toytalker_mini_v0.6.4_sw02 (Autodesk Fusion 360 design; units mm, degrees)
part number: 2026-11-13-12-19-30-729
Autodesk Fusion 360 part; units mm, degrees
ref_plane "作業平面1" through (0, 0, 0) normal (0, 0, 1) x (1, 0, 0)
sketch "スケッチ1" plane through (0, 0, 0) normal (0, 0, 1) x (1, 0, 0)
  line L0 (-1.5, -1.5) -> (41.5, -1.5)
  line L1 (41.5, -1.5) -> (41.5, 41.5)
  line L2 (41.5, 41.5) -> (-1.5, 41.5)
  line L3 (-1.5, 41.5) -> (-1.5, -1.5)
  dimension "board" = 40
  dimension "gap" = 0.2
  dimension "wall" = 1.3
  dimension "inner_h" = 9.4
  dimension "board_top" = 5
  dimension "lid_t" = 1.3
  dimension "corner_r" = 1.3
  dimension "hook_len" = 2.6
  dimension "hook_w" = 6
  dimension "hook_t" = 1
  dimension "barb" = 0.25
  dimension "groove_clear" = 0.1
  dimension "groove_h" = 1.2
  dimension "barb_h" = 0.8
  dimension "hook_root_r" = 0.3
  dimension "rim_chamfer" = 0.4
  dimension "hook_root_r_in" = 0.6
  dimension "usb_w" = 9.6
  dimension "usb_h" = 3.8
  dimension "sw_slot_l" = 3.6
  dimension "sw_slot_h" = 1.5
  dimension "btn_nub_d" = 3
  dimension "btn_clear" = 0.2
  dimension "btn_tongue_t" = 0.6
  dimension "spk_hole_d" = 1.6
  dimension "strap_hole_d" = 2
extrude "箱_押し出し" add sketch "スケッチ1" along normal blind 10.7 makes body 1
fillet "箱_角R" radius 1.3 4 edges at (-1.5, 41.5, 5.35) (41.5, 41.5, 5.35) (41.5, -1.5, 5.35) (-1.5, -1.5, 5.35) on bodies 1
shell "箱_シェル" thickness 1.3 removed faces 1 at (13.2667, 27.1667, 10.7) on bodies 1
sketch "スケッチ2" plane through (0, 0, 0) normal (1, 0, 0) x (0, 0, -1)
  line L0 (-6.065, 16.375) -> (-9.865, 16.375)
  line L1 (-9.865, 16.375) -> (-9.865, 25.975)
  line L2 (-9.865, 25.975) -> (-6.065, 25.975)
  line L3 (-6.065, 25.975) -> (-6.065, 16.375)
extrude "USB穴 (1)" cut sketch "スケッチ2" against normal blind 2 bodies 1
sketch "スケッチ3" plane through (0, 0, 0) normal (0, 1, 0) x (1, 0, 0)
  line L0 (3.62, -6.3) -> (7.22, -6.3)
  line L1 (7.22, -6.3) -> (7.22, -7.8)
  line L2 (7.22, -7.8) -> (3.62, -7.8)
  line L3 (3.62, -7.8) -> (3.62, -6.3)
extrude "スイッチ穴 (1)" cut sketch "スケッチ3" along normal blind 42 bodies 1
sketch "スケッチ4" plane through (0, 0, 0) normal (0, 1, 0) x (1, 0, 0)
  line L0 (0.92, -5.35) -> (9.92, -5.35)
  line L1 (9.92, -5.35) -> (9.92, -8.75)
  line L2 (9.92, -8.75) -> (0.92, -8.75)
  line L3 (0.92, -8.75) -> (0.92, -5.35)
extrude "スイッチくぼみ (1)" cut sketch "スケッチ4" along normal blind 0.9 from surface at 40.7 bodies 1
ref_plane "作業平面2" through (0, 0, 7.9) normal (0, 0, 1) x (1, 0, 0)
sketch "スケッチ5" plane through (0, 0, 7.9) normal (0, 0, 1) x (1, 0, 0)
  line L0 (-0.55, 28.8) -> (-0.2, 28.8)
  line L1 (-0.2, 28.8) -> (-0.2, 35.2)
  line L2 (-0.2, 35.2) -> (-0.55, 35.2)
  line L3 (-0.55, 35.2) -> (-0.55, 28.8)
  line L4 (40.2, 26.8) -> (40.55, 26.8)
  line L5 (40.55, 26.8) -> (40.55, 33.2)
  line L6 (40.55, 33.2) -> (40.2, 33.2)
  line L7 (40.2, 33.2) -> (40.2, 26.8)
  line L8 (16.8, 40.2) -> (23.2, 40.2)
  line L9 (23.2, 40.2) -> (23.2, 40.55)
  line L10 (23.2, 40.55) -> (16.8, 40.55)
  line L11 (16.8, 40.55) -> (16.8, 40.2)
  line L12 (16.8, -0.55) -> (23.2, -0.55)
  line L13 (23.2, -0.55) -> (23.2, -0.2)
  line L14 (23.2, -0.2) -> (16.8, -0.2)
  line L15 (16.8, -0.2) -> (16.8, -0.55)
extrude "爪の溝 (1)" cut sketch "スケッチ5" along normal blind 1.2 bodies 1
ref_plane "作業平面3" through (0, 0, 9.9) normal (0, 0, 1) x (1, 0, 0)
sketch "スケッチ6" plane through (0, 0, 9.9) normal (0, 0, 1) x (1, 0, 0)
  line L0 (16, -1.55) -> (24, -1.55)
  line L1 (24, -1.55) -> (24, -0.15)
  line L2 (24, -0.15) -> (16, -0.15)
  line L3 (16, -0.15) -> (16, -1.55)
extrude "指掛かり (1)" cut sketch "スケッチ6" along normal blind 0.85 bodies 1
chamfer "箱_内縁面取り" distance 0.4 angle 45 5 edges at (-0.2, 20, 10.7) (20, 40.2, 10.7) (40.2, 20, 10.7) (32.1, -0.2, 10.7) (7.9, -0.2, 10.7) tangent chain off on bodies 1
ref_plane "作業平面4" through (0, 0, 4.5) normal (0, 0, 1) x (1, 0, 0)
sketch "スケッチ7" plane through (0, 0, 4.5) normal (0, 0, 1) x (1, 0, 0)
  line L0 (41.3, 16) -> (47, 16)
  line L1 (47, 16) -> (47, 24)
  line L2 (47, 24) -> (41.3, 24)
  line L3 (41.3, 24) -> (41.3, 16)
extrude "吊り具 (1)" add sketch "スケッチ7" along normal blind 3 bodies 1
fillet "吊り具_先端R" radius 1.4 2 edges at (47, 20, 7.5) (47, 20, 4.5) on bodies 1
sketch "スケッチ8" plane through (0, 0, 0) normal (0, 1, 0) x (1, 0, 0)
  circle A0 centre (44.8, -6) radius 1
extrude "吊り穴 (1)" cut sketch "スケッチ8" along normal blind 10 from surface at 15 bodies 1
ref_plane "作業平面5" through (0, 0, 10.7) normal (0, 0, 1) x (1, 0, 0)
sketch "スケッチ9" plane through (0, 0, 10.7) normal (0, 0, 1) x (1, 0, 0)
  line L0 (-1.5, -1.5) -> (41.5, -1.5)
  line L1 (41.5, -1.5) -> (41.5, 41.5)
  line L2 (41.5, 41.5) -> (-1.5, 41.5)
  line L3 (-1.5, 41.5) -> (-1.5, -1.5)
extrude "蓋_押し出し" add sketch "スケッチ9" along normal blind 1.3 separate body makes body 2
fillet "蓋_角R" radius 1.3 4 edges at (-1.5, 41.5, 11.35) (41.5, 41.5, 11.35) (41.5, -1.5, 11.35) (-1.5, -1.5, 11.35) on bodies 2
fillet "蓋_上面R" radius 0.6 8 edges at (-1.1192, -1.1192, 12) (-1.5, 20, 12) (20, -1.5, 12) (41.1192, -1.1192, 12) (41.5, 20, 12) (41.1192, 41.1192, 12) (20, 41.5, 12) (-1.1192, 41.1192, 12) on bodies 2
ref_plane "作業平面6" through (0, 0, 10.7) normal (0, 0, 1) x (1, 0, 0)
sketch "スケッチ10" plane through (0, 0, 10.7) normal (0, 0, 1) x (1, 0, 0)
  line L0 (12.4, 16.9) -> (23.4, 16.9)
  line L1 (23.4, 16.9) -> (23.4, 30.4)
  line L2 (23.4, 30.4) -> (12.4, 30.4)
  line L3 (12.4, 30.4) -> (12.4, 16.9)
extrude "ボタン_薄肉 (1)" cut sketch "スケッチ10" along normal blind 0.7 bodies 2
ref_plane "作業平面7" through (0, 0, 10.7) normal (0, 0, 1) x (1, 0, 0)
sketch "スケッチ11" plane through (0, 0, 10.7) normal (0, 0, 1) x (1, 0, 0)
  line L0 (12.4, 16.9) -> (12.9, 16.9)
  line L1 (12.9, 16.9) -> (12.9, 29.4)
  line L2 (12.9, 29.4) -> (12.4, 29.4)
  line L3 (12.4, 29.4) -> (12.4, 16.9)
  line L4 (22.9, 16.9) -> (23.4, 16.9)
  line L5 (23.4, 16.9) -> (23.4, 29.4)
  line L6 (23.4, 29.4) -> (22.9, 29.4)
  line L7 (22.9, 29.4) -> (22.9, 16.9)
  line L8 (12.9, 16.9) -> (22.9, 16.9)
  line L9 (22.9, 16.9) -> (22.9, 17.4)
  line L10 (22.9, 17.4) -> (12.9, 17.4)
  line L11 (12.9, 17.4) -> (12.9, 16.9)
extrude "ボタン_スリット (1)" cut sketch "スケッチ11" along normal blind 1.35 bodies 2
ref_plane "作業平面8" through (0, 0, 9) normal (0, 0, 1) x (1, 0, 0)
sketch "スケッチ12" plane through (0, 0, 9) normal (0, 0, 1) x (1, 0, 0)
  circle A0 centre (17.9, 19.4) radius 1.5
extrude "ボタン_突起 (1)" add sketch "スケッチ12" along normal blind 2.4 bodies 2
ref_plane "作業平面9" through (0, 0, 10.7) normal (0, 0, 1) x (1, 0, 0)
sketch "スケッチ13" plane through (0, 0, 10.7) normal (0, 0, 1) x (1, 0, 0)
  circle A0 centre (25, 6) radius 0.8
  circle A1 centre (25, 10.5) radius 0.8
  circle A2 centre (25, 15) radius 0.8
  circle A3 centre (29.5, 6) radius 0.8
  circle A4 centre (29.5, 10.5) radius 0.8
  circle A5 centre (29.5, 15) radius 0.8
  circle A6 centre (34, 6) radius 0.8
  circle A7 centre (34, 10.5) radius 0.8
  circle A8 centre (34, 15) radius 0.8
extrude "音抜き穴 (1)" cut sketch "スケッチ13" along normal blind 1.35 bodies 2
ref_plane "作業平面10" through (0, 0, 10.7) normal (0, 0, 1) x (1, 0, 0)
sketch "スケッチ14" plane through (0, 0, 10.7) normal (0, 0, 1) x (1, 0, 0)
  line L0 (-0.1, 27) -> (0.9, 27)
  line L1 (0.9, 27) -> (0.9, 38.7)
  line L2 (0.9, 38.7) -> (-0.1, 38.7)
  line L3 (-0.1, 38.7) -> (-0.1, 27)
  line L4 (39.1, 16) -> (40.1, 16)
  line L5 (40.1, 16) -> (40.1, 38.7)
  line L6 (40.1, 38.7) -> (39.1, 38.7)
  line L7 (39.1, 38.7) -> (39.1, 16)
  line L8 (1.3, 39.1) -> (38.7, 39.1)
  line L9 (38.7, 39.1) -> (38.7, 40.1)
  line L10 (38.7, 40.1) -> (1.3, 40.1)
  line L11 (1.3, 40.1) -> (1.3, 39.1)
  line L12 (15, -0.1) -> (26, -0.1)
  line L13 (26, -0.1) -> (26, 0.9)
  line L14 (26, 0.9) -> (15, 0.9)
  line L15 (15, 0.9) -> (15, -0.1)
extrude "爪 (1)" add sketch "スケッチ14" against normal blind 2.6 bodies 2
ref_plane "作業平面11" through (0, 0, 8.1) normal (0, 0, 1) x (1, 0, 0)
sketch "スケッチ15" plane through (0, 0, 8.1) normal (0, 0, 1) x (1, 0, 0)
  line L0 (-0.45, 29) -> (-0.1, 29)
  line L1 (-0.1, 29) -> (-0.1, 35)
  line L2 (-0.1, 35) -> (-0.45, 35)
  line L3 (-0.45, 35) -> (-0.45, 29)
  line L4 (40.1, 27) -> (40.45, 27)
  line L5 (40.45, 27) -> (40.45, 33)
  line L6 (40.45, 33) -> (40.1, 33)
  line L7 (40.1, 33) -> (40.1, 27)
  line L8 (17, 40.1) -> (23, 40.1)
  line L9 (23, 40.1) -> (23, 40.45)
  line L10 (23, 40.45) -> (17, 40.45)
  line L11 (17, 40.45) -> (17, 40.1)
  line L12 (17, -0.45) -> (23, -0.45)
  line L13 (23, -0.45) -> (23, -0.1)
  line L14 (23, -0.1) -> (17, -0.1)
  line L15 (17, -0.1) -> (17, -0.45)
extrude "爪の返し (1)" add sketch "スケッチ15" along normal blind 0.8 bodies 2
chamfer "爪_導入面取り" distance 0.33 angle 45 4 edges at (20, -0.45, 8.1) (-0.45, 32, 8.1) (40.45, 30, 8.1) (20, 40.45, 8.1) tangent chain off on bodies 2
chamfer "爪_抜き面取り" distance 0.33 distance2 0.43 4 edges at (20, 40.45, 8.9) (40.45, 30, 8.9) (-0.45, 32, 8.9) (20, -0.45, 8.9) measured on face at (19, 40.2167, 8.9) measured on face at (40.2167, 31, 8.9) measured on face at (-0.3333, 33, 8.9) measured on face at (19, -0.3333, 8.9) tangent chain off on bodies 2
fillet "爪_根元R_外" radius 0.3 4 edges at (20.5, -0.1, 10.7) (-0.1, 32.85, 10.7) (40.1, 27.35, 10.7) (20, 40.1, 10.7) on bodies 2
fillet "爪_根元R_内" radius 0.6 4 edges at (20.5, 0.9, 10.7) (0.9, 32.85, 10.7) (39.1, 27.35, 10.7) (20, 39.1, 10.7) on bodies 2
sketch "スケッチ16" plane through (0, 0, 0) normal (1, 0, 0) x (0, 0, -1)
  line L0 (0, 41.4) -> (0, 43)
  line L1 (0, 43) -> (-5.25, 43)
  line L2 (-5.25, 43) -> (-4.45, 42.2)
  line L3 (-4.45, 42.2) -> (-4.45, 41.4)
  line L4 (-4.45, 41.4) -> (0, 41.4)
extrude "つまみレール (1)" add sketch "スケッチ16" along normal blind 11.6 bodies 1
sketch "スケッチ17" plane through (0, 0, 0) normal (1, 0, 0) x (0, 0, -1)
  line L0 (-12, 40.8) -> (-12, 43)
  line L1 (-12, 43) -> (-8.85, 43)
  line L2 (-8.85, 43) -> (-9.65, 42.2)
  line L3 (-9.65, 42.2) -> (-9.65, 41.6)
  line L4 (-9.65, 41.6) -> (-10.7, 41.6)
  line L5 (-10.7, 41.6) -> (-10.7, 40.8)
  line L6 (-10.7, 40.8) -> (-12, 40.8)
extrude "つまみひさし (1)" add sketch "スケッチ17" along normal blind 11.6 bodies 2
sketch "スケッチ18" plane through (0, 0, 0) normal (1, 0, 0) x (0, 0, -1)
  line L0 (-4.55, 41.6) -> (-4.55, 42.1)
  line L1 (-4.55, 42.1) -> (-5.45, 43)
  line L2 (-5.45, 43) -> (-8.65, 43)
  line L3 (-8.65, 43) -> (-9.55, 42.1)
  line L4 (-9.55, 42.1) -> (-9.55, 41.6)
  line L5 (-9.55, 41.6) -> (-4.55, 41.6)
extrude "つまみ_板 (1)" add sketch "スケッチ18" along normal blind 10 from surface at 0.42 separate body makes body 3
sketch "スケッチ19" plane through (0, 0, 0) normal (0, 1, 0) x (1, 0, 0)
  line L0 (3.17, -5.55) -> (7.67, -5.55)
  line L1 (7.67, -5.55) -> (7.67, -8.55)
  line L2 (7.67, -8.55) -> (3.17, -8.55)
  line L3 (3.17, -8.55) -> (3.17, -5.55)
extrude "つまみ_舌 (1)" add sketch "スケッチ19" along normal blind 0.85 from surface at 40.8 bodies 3
sketch "スケッチ20" plane through (0, 0, 0) normal (0, 1, 0) x (1, 0, 0)
  line L0 (4.62, -5.45) -> (6.22, -5.45)
  line L1 (6.22, -5.45) -> (6.22, -8.65)
  line L2 (6.22, -8.65) -> (4.62, -8.65)
  line L3 (4.62, -8.65) -> (4.62, -5.45)
extrude "つまみ_ノブ溝 (1)" cut sketch "スケッチ20" along normal blind 1.15 from surface at 40.7 bodies 3
sketch "スケッチ21" plane through (0, 0, 0) normal (0, 1, 0) x (1, 0, 0)
  line L0 (2.42, -5.4) -> (3.22, -5.4)
  line L1 (3.22, -5.4) -> (3.22, -8.7)
  line L2 (3.22, -8.7) -> (2.42, -8.7)
  line L3 (2.42, -8.7) -> (2.42, -5.4)
  line L4 (5.02, -5.4) -> (5.82, -5.4)
  line L5 (5.82, -5.4) -> (5.82, -8.7)
  line L6 (5.82, -8.7) -> (5.02, -8.7)
  line L7 (5.02, -8.7) -> (5.02, -5.4)
  line L8 (7.62, -5.4) -> (8.42, -5.4)
  line L9 (8.42, -5.4) -> (8.42, -8.7)
  line L10 (8.42, -8.7) -> (7.62, -8.7)
  line L11 (7.62, -8.7) -> (7.62, -5.4)
extrude "つまみ_指溝 (1)" cut sketch "スケッチ21" along normal blind 0.6 from surface at 42.5 bodies 3
equation "board = 40.0 mm" comment "基板の一辺（v0.3、40×40）"
equation "gap = 0.2 mm" comment "基板と内壁のすき間（片側）"
equation "wall = 1.3 mm" comment "側壁と底の厚さ"
equation "inner_h = 9.4 mm" comment "内寸の高さ（[電池3＋クッション1＋]基板1＋部品4＋余裕0.4。薄型は電池とクッション無し）"
equation "board_top = 5.0 mm" comment "内底から基板上面まで（[電池3＋クッション1＋]基板1）"
equation "lid_t = 1.3 mm" comment "蓋の厚さ"
equation "corner_r = 1.3 mm" comment "外形の角の丸み"
equation "hook_len = 2.6 mm" comment "蓋の爪の長さ（蓋の裏から）"
equation "hook_w = 6.0 mm" comment "蓋の爪の幅"
equation "hook_t = 1.0 mm" comment "蓋の爪の厚さ（爪は曲げない。箱の壁をたわませる）"
equation "barb = 0.25 mm" comment "返しが内壁の面から飛び出す量（= 壁をたわませる量）"
equation "groove_clear = 0.1 mm" comment "溝の深さの余裕（溝は返しよりこれだけ深い）"
equation "groove_h = 1.2 mm" comment "溝の高さ"
equation "barb_h = 0.8 mm" comment "返しの高さ（下は 45° の導入面、上は抜くときの斜面）"
equation "hook_root_r = 0.3 mm" comment "爪の根元の丸み（層の境目の応力を散らす）"
equation "rim_chamfer = 0.4 mm" comment "箱の内側の上縁の面取り（蓋の導入と、爪の根元の丸みの逃げ）"
equation "hook_root_r_in = 0.6 mm" comment "爪の根元の内側の丸み（剥がれ止め。外側は hook_root_r）"
equation "usb_w = 9.6 mm" comment "USB-C 穴の幅"
equation "usb_h = 3.8 mm" comment "USB-C 穴の高さ"
equation "sw_slot_l = 3.6 mm" comment "スライドスイッチの穴の長さ（v0.2: ノブ1.3＋動き1.5＋余裕0.8 / v0.3: ノブ1.2＋動き1.4＋余裕）"
equation "sw_slot_h = 1.5 mm" comment "スライドスイッチの穴の高さ（v0.2 は本体 1.4 の中のノブ位置が不確かなので基板上面 0..1.5 を全部開ける）"
equation "btn_nub_d = 3.0 mm" comment "ボタン突起の直径"
equation "btn_clear = 0.2 mm" comment "ボタン突起と押し子のすき間（常時）"
equation "btn_tongue_t = 0.6 mm" comment "ボタン板ばねの厚さ"
equation "spk_hole_d = 1.6 mm" comment "蓋の音抜き穴の直径"
equation "strap_hole_d = 2.0 mm" comment "吊り穴の直径"
equation "d33 = wall"
named bodies: "つまみ"
